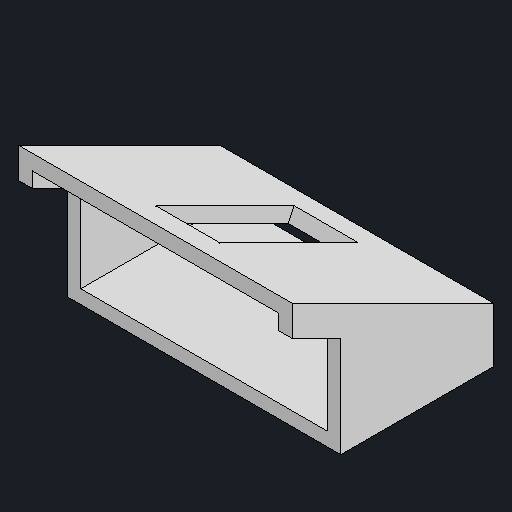
# Autodesk Inventor part: echelle-grating-mount-mockup
Saved by Autodesk Inventor 2027.1 (Build 311270010, 270A)
## iProperties
Created: 2026-11-20
Part Number: echelle-grating-mount-mockup
Material: Generic
Document SubType Name: Modeling
Designer: queezz
Density: 1 g/cm^3
Appearance: Default
Author: queezz
Autodesk Inventor part; units mm, degrees
ref_plane "YZ Plane" through (0, 0, 0) normal (1, 0, 0) x (0, 1, 0)
ref_plane "XZ Plane" through (0, 0, 0) normal (0, 1, 0) x (-1, 0, 0)
ref_plane "XY Plane" through (0, 0, 0) normal (0, 0, 1) x (1, 0, 0)
sketch "Sketch1" plane through (0, 0, 0) normal (1, 0, 0) x (0, 1, 0)
  line L0 (0, 0) -> (4.0227, 0)
  line L1 (4.0227, 0) -> (11.3434, 14.683)
  line L2 (11.3434, 14.683) -> (0, 14.683)
  line L3 (0, 14.683) -> (0, 0)
  line L4 (9.1169, 14.683) -> (7.3529, 11.1449)
  line L5 (7.3529, 11.1449) -> (0, 11.1449)
  dimension "d9" = 26.5
  constraints: 12 end point, 2 parallel, 2 perpendicular, 2 point on line, 1 horizontal
  measures "d9" angle of L3 L1
extrude "Extrusion1" add sketch "Sketch1" along normal mid plane 20 contours L3 L5 L4 L2 L1 L0
shell "Shell1" thickness 1 removed faces 2 at (3.3333, 4.9019, 11.1449) at (3.3333, 8.5289, 13.5036)
sketch "Sketch2" plane through (-9, 0, 0.1978) normal (1, 0, 0) x (0, 1, 0)
  line L0 (8.6183, 13.4853) -> (7.3529, 10.9471) projected
  line L1 (9.1169, 14.4853) -> (7.3529, 10.9471) projected
  line L2 (7.3529, 10.9471) -> (9.1169, 14.4853) projected
  line L3 (7.3529, 10.9471) -> (8.6183, 13.4853) projected
  line L4 (8.6183, 13.4853) -> (9.7274, 13.4853) projected
  line L5 (9.7274, 13.4853) -> (8.6183, 13.4853) projected
  line L6 (11.3434, 14.4853) -> (9.1169, 14.4853) projected
  line L7 (9.1169, 14.4853) -> (11.3434, 14.4853) projected
  line L8 (9.7274, 13.4853) -> (10.226, 14.4853)
  point P0 (0, -0.1978)
  point P1 (8.6183, 13.4853)
  constraints: 2 end point, 1 parallel, 1 point on line
extrude "Extrusion2" cut sketch "Sketch2" along normal up to surface (18 mm away)
sketch "Sketch3" plane through (-10, 11.3434, 14.683) normal (0, 0.8949344, -0.4461978) x (1, 0, 0)
  line L0 (7.6703, 2.6416) -> (12.3297, 2.6416)
  line L1 (12.3297, 2.6416) -> (12.3297, 13.927)
  line L2 (12.3297, 13.927) -> (7.6703, 13.927)
  line L3 (7.6703, 13.927) -> (7.6703, 2.6416)
  point P0 (10, 18.2017)
  point P1 (10, 13.927)
  constraints: 8 end point, 2 parallel, 1 horizontal, 1 midpoint, 1 perpendicular, 1 vertical alignment
extrude "Extrusion3" cut sketch "Sketch3" against normal up to surface (1 mm away)
sketch "Sketch4" plane through (-9, 3.4038, 1) normal (0, 0, 1) x (1, 0, 0)
  line L0 (0, 0) -> (18, 0) projected
  line L1 (0, 0) -> (0, -2.4038) projected
  line L2 (0, -2.4038) -> (18, -2.4038) projected
  line L3 (18, -2.4038) -> (18, 0) projected
  point P0 (9, -3.4038)
extrude "Extrusion4" cut sketch "Sketch4" against normal through all
body "Solid1"
